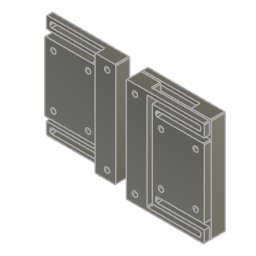
compliant_component_v1 (Autodesk Fusion 360 design; units mm, degrees)
Autodesk Fusion 360 part; units mm, degrees
sketch "Schizzo1" plane through (0, 0, 0) normal (0, 1, 0) x (1, 0, 0)
  line L0 (0, 0) -> (15, 0) construction
  line L1 (-14.5, 20) -> (0, 20)
  line L2 (-15, 0) -> (-15, 19.5)
  line L3 (0, 20) -> (0, 0) construction
  line L4 (12, 20) -> (0, 20)
  line L5 (15, 0) -> (15, 20)
  line L6 (30, 0) -> (18, 0) construction
  line L7 (30, 29.5) -> (30, 0)
  line L8 (18, 30) -> (29.5, 30)
  line L9 (18, 0) -> (18, 30) construction
  line L10 (18, 30) -> (18, 28) construction
  line L11 (30, 0) -> (18, 0) construction
  line L12 (18, 30) -> (-14.5, 30)
  line L13 (-15, 29.5) -> (-15, 23)
  line L14 (-15, 23) -> (12, 23)
  line L15 (13, 22) -> (13, 21)
  line L16 (17.5, 28) -> (-12, 28)
  line L17 (-13, 27) -> (-13, 26)
  line L18 (-12, 25) -> (15, 25)
  line L19 (15, 25) -> (15, 20)
  arc A0 (-13, 26) -> (-12, 25) centre (-12, 26) ccw
  arc A1 (-12, 28) -> (-13, 27) centre (-12, 27) ccw
  arc A2 (13, 22) -> (12, 23) centre (12, 22) ccw
  arc A3 (12, 20) -> (13, 21) centre (12, 21) ccw
  line L20 (18, 0) -> (18, 27.5)
  line L21 (-13, -27) -> (-13, -26)
  line L22 (12, -20) -> (0, -20)
  line L23 (18, 0) -> (18, -27.5) construction
  line L24 (18, -30) -> (-14.5, -30)
  line L25 (18, -30) -> (18, -28) construction
  arc A4 (12, -23) -> (13, -22) centre (12, -22) ccw
  line L26 (17.5, -28) -> (-12, -28)
  line L27 (13, -22) -> (13, -21)
  line L28 (-12, -25) -> (15, -25)
  line L29 (18, -30) -> (29.5, -30)
  line L30 (-14.5, -20) -> (0, -20)
  arc A5 (-13, -27) -> (-12, -28) centre (-12, -27) ccw
  line L31 (-15, -23) -> (12, -23)
  arc A6 (-12, -25) -> (-13, -26) centre (-12, -26) ccw
  arc A7 (13, -21) -> (12, -20) centre (12, -21) ccw
  line L32 (30, -29.5) -> (30, 0)
  line L33 (15, -25) -> (15, -20)
  line L34 (-15, -29.5) -> (-15, -23)
  line L35 (15, 0) -> (15, -20)
  line L36 (0, -20) -> (0, 0) construction
  line L37 (18, 0) -> (18, -28)
  line L38 (-15, 0) -> (-15, -19.5)
  arc A8 (17.5, -28) -> (18, -27.5) centre (17.5, -27.5) ccw
  arc A9 (18, 27.5) -> (17.5, 28) centre (17.5, 27.5) ccw
  arc A10 (-15, -29.5) -> (-14.5, -30) centre (-14.5, -29.5) ccw
  arc A11 (29.5, -30) -> (30, -29.5) centre (29.5, -29.5) ccw
  arc A12 (30, 29.5) -> (29.5, 30) centre (29.5, 29.5) ccw
  arc A13 (-14.5, 30) -> (-15, 29.5) centre (-14.5, 29.5) ccw
  arc A14 (-15, -19.5) -> (-14.5, -20) centre (-14.5, -19.5) ccw
  arc A15 (-14.5, 20) -> (-15, 19.5) centre (-14.5, 19.5) ccw
  point P0 (15, 20)
  point P1 (-15, 30)
  point P2 (15, -20)
  dimension "d3" = 15
  dimension "d5" = 7
  dimension "d6" = 1
  dimension "d9" = 0.5
  dimension "d10" = 0.5
  dimension "d11" = 0.5
  constraint horizontal L0
  constraint coincident L0.start L3.end
  constraint symmetric L3.end L0 L36.end
  constraint symmetric L1.end L3 L4.end
  constraint symmetric L2.start L3 L0.end
  constraint horizontal L6
  constraint symmetric L7.end L6 L11.start
  constraint symmetric L9.start L6 L11.end
  constraint perpendicular L4 L13
  constraint perpendicular L9 L14
  constraint perpendicular L4 L15
  constraint perpendicular L9 L16
  constraint perpendicular L16 L17
  constraint perpendicular L9 L18
  constraint tangent L17 A0
  constraint tangent L18 A0
  constraint tangent L16 A1
  constraint tangent L17 A1
  constraint equal A0 A1
  constraint tangent L14 A2
  constraint tangent L15 A2
  constraint equal A0 A2
  constraint coincident P0 L4
  constraint tangent L4 A3
  constraint tangent L15 A3
  constraint equal A0 A3
  constraint coincident L10.end L9
  constraint symmetric L0 L1.end L22.end
  constraint symmetric L0 P0 P2
  constraint symmetric L0 L2.start L38.start
  constraint symmetric L0 L3.end L36.end
  constraint symmetric L0 L5.start L35.start
  constraint symmetric L0 L6.end L9.start
  constraint symmetric L0 L10.end L25.end
  constraint symmetric L0 L8.start L24.start
  constraint symmetric L0 L6.start L7.end
  constraint symmetric L0 L13.end L31.start
  constraint symmetric L0 L18.end L28.end
  constraint symmetric L0 L17.end L21.end
  constraint symmetric L0 L18.start L28.start
  constraint symmetric L0 A0 A6
  constraint symmetric L0 L16.end L26.end
  constraint symmetric L0 L17.start L21.start
  constraint symmetric L0 A1 A5
  constraint symmetric L0 L14.end A4.start
  constraint symmetric L0 L15.start A4.end
  constraint symmetric L0 A2 A4
  constraint symmetric L0 L4.start L22.start
  constraint symmetric L0 L15.end L27.end
  constraint symmetric L0 A3 A7
  constraint coincident L25.end L26
  constraint coincident L24.start L23
  constraint tangent L26 A8
  constraint tangent L23 A8
  constraint coincident L10.end L16
  constraint coincident L10.end L20
  constraint tangent L16 A9
  constraint tangent L20 A9
  constraint tangent L24 A10
  constraint tangent L34 A10
  constraint tangent L29 A11
  constraint tangent L32 A11
  constraint equal A10 A11
  constraint tangent L7 A12
  constraint tangent L8 A12
  constraint equal A10 A12
  constraint coincident P1 L12
  constraint coincident P1 L13
  constraint tangent L12 A13
  constraint tangent L13 A13
  constraint equal A10 A13
  constraint tangent L30 A14
  constraint tangent L38 A14
  constraint equal A10 A14
  constraint tangent L1 A15
  constraint tangent L2 A15
  constraint equal A10 A15
  measures "d3" distance of L0.start L0.end
  measures "d5" distance of P1 L13.end
  measures "d6" radius of A0
  measures "d9" radius of A8
  measures "d10" radius of A9
  measures "d11" radius of A10
extrude "Estrusione1" add sketch "Schizzo1" along normal blind 3 makes body 1 in component "Component"
sketch "Schizzo2" plane through (0, 0, 0) normal (0, -1, 0) x (1, 0, 0)
  line L0 (18, 27.5) -> (18, -27.5)
  arc A0 (17.5, -28) -> (18, -27.5) centre (17.5, -27.5) ccw
  line L1 (17.5, -28) -> (-12, -28)
  arc A1 (-13, -27) -> (-12, -28) centre (-12, -27) ccw
  line L2 (-13, -27) -> (-13, -26)
  arc A2 (-12, -25) -> (-13, -26) centre (-12, -26) ccw
  line L3 (-12, -25) -> (15, -25)
  line L4 (15, -25) -> (15, -20)
  line L5 (15, -20) -> (15, 20)
  line L6 (15, 20) -> (15, 25)
  line L7 (15, 25) -> (-12, 25)
  arc A3 (-13, 26) -> (-12, 25) centre (-12, 26) ccw
  line L8 (-13, 26) -> (-13, 27)
  arc A4 (-12, 28) -> (-13, 27) centre (-12, 27) ccw
  line L9 (-12, 28) -> (17.5, 28)
  arc A5 (18, 27.5) -> (17.5, 28) centre (17.5, 27.5) ccw
  line L10 (-14.5, -20) -> (12, -20)
  arc A6 (13, -21) -> (12, -20) centre (12, -21) ccw
  line L11 (13, -21) -> (13, -22)
  arc A7 (12, -23) -> (13, -22) centre (12, -22) ccw
  line L12 (12, -23) -> (-15, -23)
  line L13 (-15, -23) -> (-15, -29.5)
  arc A8 (-15, -29.5) -> (-14.5, -30) centre (-14.5, -29.5) ccw
  line L14 (-14.5, -30) -> (29.5, -30)
  arc A9 (29.5, -30) -> (30, -29.5) centre (29.5, -29.5) ccw
  line L15 (30, -29.5) -> (30, 29.5)
  arc A10 (30, 29.5) -> (29.5, 30) centre (29.5, 29.5) ccw
  line L16 (29.5, 30) -> (-14.5, 30)
  arc A11 (-14.5, 30) -> (-15, 29.5) centre (-14.5, 29.5) ccw
  line L17 (-15, 29.5) -> (-15, 23)
  line L18 (-15, 23) -> (12, 23)
  arc A12 (13, 22) -> (12, 23) centre (12, 22) ccw
  line L19 (13, 22) -> (13, 21)
  arc A13 (12, 20) -> (13, 21) centre (12, 21) ccw
  line L20 (12, 20) -> (-14.5, 20)
  arc A14 (-14.5, 20) -> (-15, 19.5) centre (-14.5, 19.5) ccw
  line L21 (-15, 19.5) -> (-15, -19.5)
  arc A15 (-15, -19.5) -> (-14.5, -20) centre (-14.5, -19.5) ccw
  line L22 (-14.5, 20) -> (14.5, 20)
  line L23 (15, 19.5) -> (15, -19.5)
  line L24 (14.5, -20) -> (-14.5, -20)
  line L25 (-15, -19.5) -> (-15, 19.5)
  arc A16 (-14.5, 20) -> (-15, 19.5) centre (-14.5, 19.5) ccw
  arc A17 (15, 19.5) -> (14.5, 20) centre (14.5, 19.5) ccw
  arc A18 (14.5, -20) -> (15, -19.5) centre (14.5, -19.5) ccw
  arc A19 (-15, -19.5) -> (-14.5, -20) centre (-14.5, -19.5) ccw
  line L26 (29.5, 30) -> (18.5, 30)
  line L27 (18, 29.5) -> (18, -29.5)
  line L28 (18.5, -30) -> (29.5, -30)
  line L29 (30, -29.5) -> (30, 29.5)
  arc A20 (29.5, -30) -> (30, -29.5) centre (29.5, -29.5) ccw
  arc A21 (18, -29.5) -> (18.5, -30) centre (18.5, -29.5) ccw
  arc A22 (30, 29.5) -> (29.5, 30) centre (29.5, 29.5) ccw
  arc A23 (18.5, 30) -> (18, 29.5) centre (18.5, 29.5) ccw
  line L30 (-15, 20) -> (15, -20) construction
  line L31 (15, 20) -> (-15, -20) construction
  circle A24 centre (-10, -15) radius 1.5
  line L32 (0, -20) -> (0, 0) construction
  circle A25 centre (10, -15) radius 1.5
  line L33 (0, 0) -> (15, 0) construction
  circle A26 centre (-10, 15) radius 1.5
  circle A27 centre (10, 15) radius 1.5
  circle A28 centre (25, 25) radius 1.5
  circle A29 centre (25, -25) radius 1.5
  dimension "d12" = 0.5
  dimension "d15" = 0.5
  dimension "d18" = 3
  dimension "d19" = 3
  dimension "d20" = 3
  constraint horizontal L22
  constraint vertical L23
  constraint horizontal L24
  constraint vertical L25
  constraint tangent L22 A16
  constraint tangent L25 A16
  constraint tangent L22 A17
  constraint tangent L23 A17
  constraint equal A16 A17
  constraint tangent L23 A18
  constraint tangent L24 A18
  constraint equal A16 A18
  constraint tangent L24 A19
  constraint tangent L25 A19
  constraint equal A16 A19
  constraint horizontal L26
  constraint vertical L27
  constraint horizontal L28
  constraint vertical L29
  constraint tangent L28 A20
  constraint tangent L29 A20
  constraint tangent L27 A21
  constraint tangent L28 A21
  constraint equal A20 A21
  constraint tangent L26 A22
  constraint tangent L29 A22
  constraint equal A20 A22
  constraint tangent L26 A23
  constraint tangent L27 A23
  constraint equal A20 A23
  constraint coincident L4.end L5.start
  constraint coincident L5.end L6.start
  constraint symmetric A24 L32 A25
  constraint symmetric A24 L33 A26
  constraint symmetric A25 L33 A27
  measures "d12" radius of A16
  measures "d15" radius of A20
  measures "d18" diameter of A24
  measures "d19" diameter of A28
  measures "d20" diameter of A29
extrude "Estrusione2" add sketch "Schizzo2" along normal blind 1 contours L5 L10 L20 A14 L21 A15 L22 L23 L24 L25 A16 A17 A18 A19 | A24 | A25 | A26 | A27 bodies 1 in component "Component"
extrude "Estrusione3" add sketch "Schizzo2" along normal blind 5 contours L0 L14 A9 L15 A10 L16 L26 L27 L28 L29 A20 A21 A22 A23 | A28 | A29 bodies 1 in component "Component"
extrude "Estrusione4" cut sketch "Schizzo2" along normal blind 17 and the other way blind 21 contours A24 | A25 | A26 | A27 | A28 | A29 bodies 1 in component "Component"
extrude "Estrusione1'" add sketch "Schizzo1" along normal blind 3 separate body makes body 2 in component "Component'"
extrude "Estrusione2'" add sketch "Schizzo2" along normal blind 1 contours L5 L10 L20 A14 L21 A15 L22 L23 L24 L25 A16 A17 A18 A19 | A24 | A25 | A26 | A27 bodies 2 in component "Component'"
extrude "Estrusione3'" add sketch "Schizzo2" along normal blind 5 contours L0 L14 A9 L15 A10 L16 L26 L27 L28 L29 A20 A21 A22 A23 | A28 | A29 bodies 2 in component "Component'"
extrude "Estrusione4'" cut sketch "Schizzo2" along normal blind 17 and the other way blind 21 contours A24 | A25 | A26 | A27 | A28 | A29 bodies 2 in component "Component'"
component "Component" placed x (1, 0, 0) y (0, 1, 0) z (0, 0, 1) at (0, 0, 0)
component "Component" placed x (1, 0, 0) y (0, 1, 0) z (0, 0, 1) at (-55, 0, 0)
component "Component'" placed x (1, 0, 0) y (0, 1, 0) z (0, 0, 1) at (-55, 0, 0)
